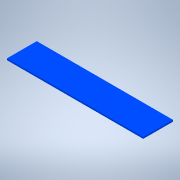
# Autodesk Inventor part: jumatate_tablie_pat_sus_picioare
Saved by Autodesk Inventor 2022.6 (Build 266554000, 554)
## iProperties
Created: 2026-10-23
Part Number: jumatate_tablie_pat_sus_picioare
Material: Generic
Document SubType Name: Modeling
Designer: Dragos Macovei
Density: 1 g/cm^3
Appearance: Default
Author: Dragos Macovei
Autodesk Inventor part; units mm, degrees
ref_plane "YZ Plane" through (0, 0, 0) normal (1, 0, 0) x (0, 1, 0)
ref_plane "XZ Plane" through (0, 0, 0) normal (0, 1, 0) x (-1, 0, 0)
ref_plane "XY Plane" through (0, 0, 0) normal (0, 0, 1) x (1, 0, 0)
sketch "Sketch1" plane through (0, 0, 0) normal (0, 1, 0) x (-1, 0, 0)
  line L0 (0, 0) -> (1542, 0)
  line L1 (1542, 0) -> (1542, 337)
  line L2 (1542, 337) -> (0, 337)
  line L3 (0, 337) -> (0, 0)
  line L4 (1542, 337) -> (1418, 337)
  line L5 (1542, 239) -> (1542, 337)
  dimension "d0" = 1542
  dimension "d1" = 337
  constraints: 12 end point, 2 horizontal, 2 parallel, 1 coincident, 1 perpendicular
  measures "d0" distance of L2.end L1.end
  measures "d1" distance of L1.end L0.end
extrude "Extrusion1" add sketch "Sketch1" along normal blind 18
body "Solid1"
